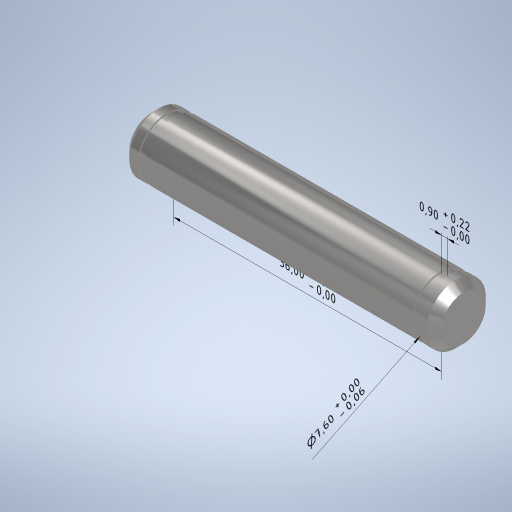
# Autodesk Inventor part: As
Saved by Autodesk Inventor 2023.2 (Build 272271000, 271)
## iProperties
Created: 2023-06-25
Part Number: As
Material: Steel, Mild
Document SubType Name: Modeling
Designer: Jeroen
Density: 7.85 g/cm^3
Appearance: Semi-Polished
Author: Jeroen
Autodesk Inventor part; units mm, degrees
ref_plane "YZ Plane" through (0, 0, 0) normal (1, 0, 0) x (0, 1, 0)
ref_plane "XZ Plane" through (0, 0, 0) normal (0, 1, 0) x (-1, 0, 0)
ref_plane "XY Plane" through (0, 0, 0) normal (0, 0, 1) x (1, 0, 0)
sketch "Sketch1" plane through (0, 0, 0) normal (0, 0, 1) x (1, 0, 0)
  line L0 (0, 0) -> (0, 3)
  line L1 (2.1, 4) -> (2.1, 3.8)
  line L2 (2.1, 3.8) -> (3, 3.8)
  line L3 (3, 3.8) -> (3, 4)
  line L4 (3, 4) -> (39, 4)
  line L5 (39, 4) -> (39, 3.8)
  line L6 (39, 3.8) -> (39.9, 3.8)
  line L7 (39.9, 3.8) -> (39.9, 4)
  line L8 (42, 3) -> (42, 0)
  line L9 (42, 0) -> (0, 0)
  line L10 (1, 4) -> (2.1, 4)
  line L11 (39.9, 4) -> (41, 4)
  line L12 (41, 4) -> (42, 3)
  line L13 (21, 0) -> (21, 4) construction
  line L14 (1, 4) -> (0, 3)
  dimension "d0" = 42
  dimension "d1" = 36
  dimension "d5" = 0.9
  dimension "d20" = 8
  dimension "d21" = 7.6
  dimension "d24" = 1
  dimension "d25" = 1
  dimension "d26" = 1
  dimension "d27" = 1
  constraints: 30 end point, 5 perpendicular, 3 collinear, 3 point on line, 2 midpoint, 2 vertical, 1 parallel
  measures "d0" distance between parallel lines of L8 L0
  measures "d1" distance between parallel lines of L5 L3
  measures "d5" distance of L1.end L2.end
  measures "d20" diameter of L10 L9
  measures "d21" diameter of L2 L9
  measures "d24" horizontal distance of L8.start L11.end
  measures "d25" horizontal distance of L8.start L11.end
  measures "d26" horizontal distance of L10.start L0.end
  measures "d27" horizontal distance of L10.start L0.end
revolve "Revolution1" add sketch "Sketch1" angle 360 about axis through (42, 0, 0) along (-1, 0, 0)
equation "\"d25\" = d24"
equation "\"d26\" = d24"
equation "\"d27\" = d26"
body "Solid1"
